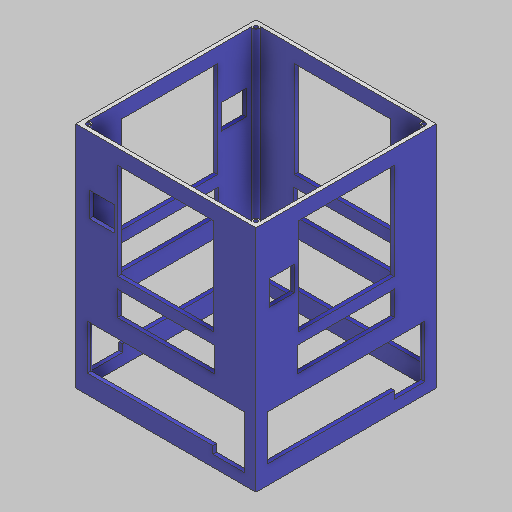
# Autodesk Inventor part: Armadura_externa
Saved by Autodesk Inventor 2027 (Build 310192000, 192)
## iProperties
Created: 2026-11-23
Part Number: Armadura_externa
Material: Genérico
Document SubType Name: Modeling
Designer: Alexander
Density: 1 g/cm^3
Appearance: Valor por defecto
Author: Alexander
Autodesk Inventor part; units mm, degrees
ref_plane "YZ Plane" through (0, 0, 0) normal (1, 0, 0) x (0, 1, 0)
ref_plane "XZ Plane" through (0, 0, 0) normal (0, 1, 0) x (-1, 0, 0)
ref_plane "XY Plane" through (0, 0, 0) normal (0, 0, 1) x (1, 0, 0)
sketch "Boceto1" plane through (0, 0, 0) normal (0, 1, 0) x (-1, 0, 0)
  line L0 (120, 120) -> (-120, 120)
  line L1 (-120, 120) -> (-120, -120)
  line L2 (-120, -120) -> (120, -120)
  line L3 (120, -120) -> (120, 120)
  line L4 (115, 115) -> (-115, 115)
  line L5 (-115, 115) -> (-115, -115)
  line L6 (-115, -115) -> (115, -115)
  line L7 (115, -115) -> (115, 115)
  circle A0 centre (112, 112) radius 2.5
  circle A1 centre (112, -112) radius 2.5
  circle A2 centre (-112, -112) radius 2.5
  circle A3 centre (-112, 112) radius 2.5
  circle A4 centre (112, 112) radius 4
  circle A5 centre (-112, 112) radius 4
  circle A6 centre (-112, -112) radius 4
  circle A7 centre (112, -112) radius 4
  point P0 (0, 0)
  point P1 (109.3542, -115)
  point P2 (-109.3542, -115)
  point P3 (-115, -109.3542)
  point P4 (-115, 109.3542)
  point P5 (-109.3542, 115)
  point P6 (109.3542, 115)
  point P7 (115, 109.3542)
  point P8 (115, -109.3542)
  dimension "d0" = 240
  dimension "d1" = 240
  dimension "d2" = 120
  dimension "d3" = 120
  dimension "d4" = 5
  dimension "d5" = 5
  dimension "d6" = 5
  dimension "d7" = 5
  dimension "d8" = 5
  dimension "d9" = 5
  dimension "d10" = 5
  dimension "d11" = 5
  dimension "d12" = 8
  dimension "d13" = 8
  dimension "d14" = 8
  dimension "d15" = 8
  dimension "d16" = 8
  dimension "d17" = 8
  dimension "d18" = 8
  dimension "d19" = 8
  dimension "d20" = 8
  dimension "d21" = 8
  dimension "d22" = 8
  dimension "d23" = 8
  constraints: 16 end point, 8 centre point, 4 coincident, 4 parallel, 2 horizontal, 2 perpendicular
  measures "d0" distance of L2.end L0.start
  measures "d1" distance of L1.end L2.end
  measures "d2" distance from line of point (0, 0) L3
  measures "d3" distance from line of point (0, 0) L2
  measures "d4" distance between parallel lines of L6 L2
  measures "d5" distance between parallel lines of L5 L1
  measures "d6" distance between parallel lines of L4 L0
  measures "d7" distance between parallel lines of L7 L3
  measures "d8" diameter of A0
  measures "d9" diameter of A1
  measures "d10" diameter of A2
  measures "d11" diameter of A3
  measures "d12" distance from line of L3 A0.centre
  measures "d13" distance from line of L0 A0.centre
  measures "d14" distance from line of L0 A3.centre
  measures "d15" distance from line of L1 A3.centre
  measures "d16" distance from line of L1 A2.centre
  measures "d17" distance from line of L2 A2.centre
  measures "d18" distance from line of L3 A1.centre
  measures "d19" distance from line of L2 A1.centre
  measures "d20" diameter of A4
  measures "d21" diameter of A5
  measures "d22" diameter of A6
  measures "d23" diameter of A7
extrude "Extrusión1" add sketch "Boceto1" along normal blind 340 contours L3 L2 L1 L0 | L7 A4 L4 | A4 L7 L4 | L4 A4 | A4 L7 | A5 L5 L4 | L4 A5 | A7 L7 | L7 A7 L6 | A5 L5 L4 | L7 L6 A7 | L6 A7 | L5 A5 | A6 L6 | L6 A6 L5 | L5 A6 | L6 L5 A6
sketch "Boceto2" plane through (120, 0, 120) normal (1, 0, 0) x (0, 0, -1)
  line L0 (0, 0) -> (240, 0) projected
  line L1 (0, 0) -> (0, 340) projected
  line L2 (240, 0) -> (240, 340) projected
  line L3 (56, 157) -> (184, 157)
  line L4 (184, 157) -> (184, 285)
  line L5 (184, 285) -> (56, 285)
  line L6 (56, 285) -> (56, 157)
  line L7 (55.25, 142) -> (184.75, 142)
  line L8 (184.75, 142) -> (184.75, 109)
  line L9 (184.75, 109) -> (55.25, 109)
  line L10 (55.25, 109) -> (55.25, 142)
  line L11 (15, 85) -> (225, 85)
  line L12 (225, 85) -> (225, 15)
  line L13 (225, 15) -> (15, 15)
  line L14 (15, 15) -> (15, 85)
  line L15 (15, 15) -> (184.75, 15)
  line L16 (184.75, 15) -> (184.75, 25)
  line L17 (184.75, 25) -> (15, 25)
  line L18 (15, 25) -> (15, 15)
  line L19 (51, 204.5) -> (18, 204.5)
  line L20 (18, 204.5) -> (18, 237.5)
  line L21 (18, 237.5) -> (51, 237.5)
  line L22 (51, 237.5) -> (51, 204.5)
  line L23 (184.75, 15) -> (225, 15)
  line L24 (225, 15) -> (225, 25)
  line L25 (225, 25) -> (184.75, 25)
  line L26 (184.75, 25) -> (184.75, 15)
  line L27 (15, 15) -> (57.5, 15)
  line L28 (57.5, 15) -> (57.5, 25)
  line L29 (57.5, 25) -> (15, 25)
  line L30 (15, 25) -> (15, 15)
  line L31 (222, 237.5) -> (189, 237.5)
  line L32 (189, 237.5) -> (189, 204.5)
  line L33 (189, 204.5) -> (222, 204.5)
  line L34 (222, 204.5) -> (222, 237.5)
  point P0 (120, 0)
  point P1 (15, 25)
  point P2 (184.75, 15)
  dimension "d26" = 157
  dimension "d27" = 285
  dimension "d28" = 184
  dimension "d29" = 184
  dimension "d30" = 129.5
  dimension "d31" = 33
  dimension "d32" = 109
  dimension "d33" = 55.25
  dimension "d34" = 15
  dimension "d35" = 15
  dimension "d36" = 10
  dimension "d37" = 33
  dimension "d38" = 33
  dimension "d39" = 5
  dimension "d41" = 42.5
  dimension "d42" = 33
  dimension "d43" = 33
  dimension "d45" = 5
  dimension "d70" = 85
  dimension "d71" = 15
  dimension "d102" = 47.5
  dimension "d103" = 47.5
  constraints: 64 end point, 16 parallel, 8 horizontal, 8 perpendicular, 2 point on line
  measures "d26" distance from line of L0 L3.start
  measures "d27" distance from line of L0 L4.end
  measures "d28" distance from line of L1 L4.end
  measures "d29" distance from line of L3.start L2
  measures "d30" distance of L8.end L9.end
  measures "d31" distance of L7.end L8.end
  measures "d32" distance between parallel lines of L0 L9
  measures "d33" distance between parallel lines of L2 L8
  measures "d34" distance between parallel lines of L12 L2
  measures "d35" distance between parallel lines of L14 L1
  measures "d36" distance of L16.end L15.end
  measures "d37" distance of L20.end L21.end
  measures "d38" distance of L19.end L20.end
  measures "d39" distance between parallel lines of L6 L22
  measures "d41" distance of L29.end L28.end
  measures "d42" distance of L33.end L32.end
  measures "d43" distance of L32.end L31.end
  measures "d45" distance between parallel lines of L4 L32
  measures "d70" distance between parallel lines of L0 L11
  measures "d71" distance between parallel lines of L0 L13
  measures "d102" distance between parallel lines of L33 L3
  measures "d103" distance between parallel lines of L3 L19
extrude "Extrusión2" cut sketch "Boceto2" against normal blind 340 contours L6 L5 L4 L3 | L7 L8 L9 L10 | L11 L12 L25 L17 L14
extrude "Extrusión3" cut sketch "Boceto2" against normal blind 120 contours L12 L13 L16 L25 | L19 L20 L21 L22
sketch "Boceto3" plane through (-120, 0, -120) normal (-1, 0, 0) x (0, 0, 1)
  line L0 (51, 204.5) -> (18, 204.5)
  line L1 (18, 204.5) -> (18, 237.5)
  line L2 (18, 237.5) -> (51, 237.5)
  line L3 (51, 237.5) -> (51, 204.5)
  line L4 (56, 157) -> (56, 285) projected
  line L5 (56, 285) -> (184, 285) projected
  line L6 (184, 157) -> (56, 157) projected
  point P0 (120, 0)
  dimension "d50" = 33
  dimension "d51" = 33
  dimension "d52" = 5
  dimension "d104" = 47.5
  constraints: 8 end point, 2 parallel, 1 horizontal, 1 perpendicular
  measures "d50" distance of L1.end L2.end
  measures "d51" distance of L0.end L1.end
  measures "d52" distance between parallel lines of L4 L3
  measures "d104" distance between parallel lines of L6 L0
extrude "Extrusión4" cut sketch "Boceto3" against normal blind 120
sketch "Boceto4" plane through (-120, 0, -120) normal (-1, 0, 0) x (0, 0, 1)
  line L0 (225, 25) -> (15, 25) projected
  line L1 (225, 25) -> (182.5, 25)
  line L2 (182.5, 25) -> (182.5, 15)
  line L3 (182.5, 15) -> (225, 15)
  line L4 (225, 15) -> (225, 25)
  point P0 (120, 0)
  point P1 (182.5, 25)
  dimension "d56" = 42.5
  dimension "d57" = 10
  constraints: 8 end point, 2 parallel, 1 horizontal, 1 perpendicular
  measures "d56" distance of L3.end L2.end
  measures "d57" distance of L2.end L1.end
extrude "Extrusión5" cut sketch "Boceto4" against normal blind 120
sketch "Boceto5" plane through (120, 0, -120) normal (0, 0, -1) x (-1, 0, 0)
  line L0 (56, 285) -> (184, 285)
  line L1 (184, 285) -> (184, 157)
  line L2 (184, 157) -> (56, 157)
  line L3 (56, 157) -> (56, 285)
  line L4 (0, 0) -> (240, 0) projected
  line L5 (240, 0) -> (240, 340) projected
  line L6 (55.25, 142) -> (184.75, 142)
  line L7 (184.75, 142) -> (184.75, 109)
  line L8 (184.75, 109) -> (55.25, 109)
  line L9 (55.25, 109) -> (55.25, 142)
  line L10 (15, 85) -> (225, 85)
  line L11 (225, 85) -> (225, 15)
  line L12 (225, 15) -> (15, 15)
  line L13 (15, 15) -> (15, 85)
  line L14 (0, 0) -> (0, 340) projected
  line L15 (15, 15) -> (57.5, 15)
  line L16 (57.5, 15) -> (57.5, 25)
  line L17 (57.5, 25) -> (15, 25)
  line L18 (15, 25) -> (15, 15)
  line L19 (225, 15) -> (182.5, 15)
  line L20 (182.5, 15) -> (182.5, 25)
  line L21 (182.5, 25) -> (225, 25)
  line L22 (225, 25) -> (225, 15)
  line L23 (57.5, 25) -> (182.5, 25)
  line L24 (182.5, 25) -> (182.5, 15)
  line L25 (182.5, 15) -> (57.5, 15)
  line L26 (57.5, 15) -> (57.5, 25)
  line L27 (189, 204.5) -> (222, 204.5)
  line L28 (222, 204.5) -> (222, 237.5)
  line L29 (222, 237.5) -> (189, 237.5)
  line L30 (189, 237.5) -> (189, 204.5)
  line L31 (18, 237.5) -> (51, 237.5)
  line L32 (51, 237.5) -> (51, 204.5)
  line L33 (51, 204.5) -> (18, 204.5)
  line L34 (18, 204.5) -> (18, 237.5)
  point P0 (120, 0)
  dimension "d60" = 128
  dimension "d61" = 128
  dimension "d62" = 285
  dimension "d63" = 184
  dimension "d64" = 129.5
  dimension "d65" = 33
  dimension "d66" = 55.25
  dimension "d67" = 109
  dimension "d68" = 15
  dimension "d69" = 15
  dimension "d72" = 15
  dimension "d73" = 85
  dimension "d74" = 42.5
  dimension "d75" = 10
  dimension "d76" = 42.5
  dimension "d77" = 10
  dimension "d78" = 33
  dimension "d79" = 33
  dimension "d80" = 33
  dimension "d81" = 33
  dimension "d82" = 5
  dimension "d84" = 5
  dimension "d100" = 47.5
  dimension "d101" = 47.5
  constraints: 64 end point, 16 parallel, 8 horizontal, 8 perpendicular
  measures "d60" distance of L1.end L2.end
  measures "d61" distance of L0.end L1.end
  measures "d62" distance between parallel lines of L4 L0
  measures "d63" distance between parallel lines of L5 L3
  measures "d64" distance of L7.end L8.end
  measures "d65" distance of L6.end L7.end
  measures "d66" distance between parallel lines of L5 L7
  measures "d67" distance between parallel lines of L4 L8
  measures "d68" distance between parallel lines of L13 L14
  measures "d69" distance between parallel lines of L11 L5
  measures "d72" distance between parallel lines of L4 L12
  measures "d73" distance between parallel lines of L4 L10
  measures "d74" distance of L17.end L16.end
  measures "d75" distance of L16.end L15.end
  measures "d76" distance of L20.end L21.end
  measures "d77" distance of L19.end L20.end
  measures "d78" distance of L29.end L28.end
  measures "d79" distance of L28.end L27.end
  measures "d80" distance of L32.end L33.end
  measures "d81" distance of L31.end L32.end
  measures "d82" distance between parallel lines of L3 L32
  measures "d84" distance between parallel lines of L30 L1
  measures "d100" distance between parallel lines of L2 L33
  measures "d101" distance between parallel lines of L27 L2
extrude "Extrusión6" cut sketch "Boceto5" against normal blind 441.25 contours L0 L1 L2 L3 | L6 L7 L8 L9 | L10 L11 L21 L23 L17 L13
extrude "Extrusión7" cut sketch "Boceto5" against normal blind 112.75 contours L11 L12 L20 L21 | L31 L32 L33 L34
sketch "Boceto6" plane through (-120, 0, 120) normal (0, 0, 1) x (1, 0, 0)
  line L0 (57.5, 25) -> (225, 25) projected
  line L1 (225, 25) -> (182.5, 25)
  line L2 (182.5, 25) -> (182.5, 15)
  line L3 (182.5, 15) -> (225, 15)
  line L4 (225, 15) -> (225, 25)
  line L5 (51, 204.5) -> (18, 204.5)
  line L6 (18, 204.5) -> (18, 237.5)
  line L7 (18, 237.5) -> (51, 237.5)
  line L8 (51, 237.5) -> (51, 204.5)
  line L9 (56, 157) -> (56, 285) projected
  line L10 (56, 285) -> (184, 285) projected
  line L11 (184, 157) -> (56, 157) projected
  point P0 (120, 0)
  point P1 (34.5, 204.5)
  dimension "d90" = 42.5
  dimension "d91" = 10
  dimension "d92" = 33
  dimension "d93" = 33
  dimension "d94" = 5
  dimension "d99" = 47.5
  constraints: 16 end point, 4 parallel, 2 horizontal, 2 perpendicular, 1 midpoint
  measures "d90" distance of L3.end L2.end
  measures "d91" distance of L2.end L1.end
  measures "d92" distance of L6.end L7.end
  measures "d93" distance of L5.end L6.end
  measures "d94" distance between parallel lines of L8 L9
  measures "d99" distance between parallel lines of L11 L5
extrude "Extrusión8" cut sketch "Boceto6" against normal blind 112.75
sketch "Boceto7" plane through (-120, 0, -120) normal (-1, 0, 0) x (0, 0, 1)
  line L0 (240, 285) -> (240, 157) projected
  line L1 (0, 0) -> (0, 340) projected
  line L2 (240, 285) -> (0, 285)
  line L3 (0, 285) -> (0, 305)
  line L4 (0, 305) -> (240, 305)
  line L5 (240, 305) -> (240, 285)
  line L6 (0, 340) -> (240, 340)
  line L7 (240, 340) -> (240, 305)
  line L8 (240, 305) -> (0, 305)
  line L9 (0, 305) -> (0, 340)
  point P0 (120, 0)
  dimension "d105" = 20
  constraints: 16 end point, 4 parallel, 2 horizontal, 2 perpendicular, 1 point on line
  measures "d105" distance of L2.end L3.end
extrude "Extrusión9" cut sketch "Boceto7" against normal blind 300 contours L1 L6 L7 L4
equation "\"d2\" = 0.5 * d1"
equation "\"d3\" = 0.5 * d0"
